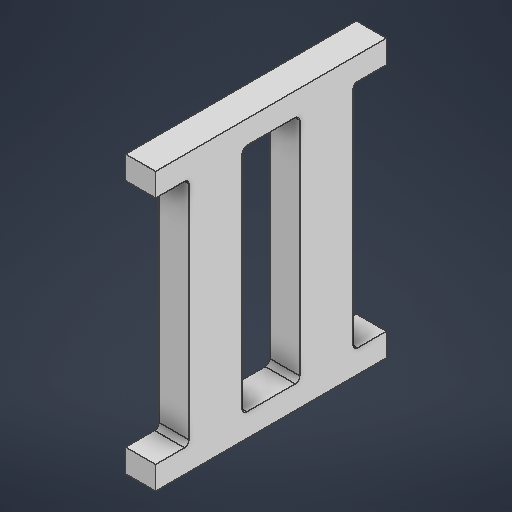
# Autodesk Inventor part: baseCorredera
Saved by Autodesk Inventor 2027.1 (Build 311270010, 270A)
## iProperties
Created: 2026-11-02
Part Number: baseCorredera
Material: Genérico
Document SubType Name: Modeling
Designer: MANGEL
Density: 1 g/cm^3
Appearance: Valor por defecto
Author: MANGEL
Autodesk Inventor part; units mm, degrees
ref_plane "YZ Plane" through (0, 0, 0) normal (1, 0, 0) x (0, 1, 0)
ref_plane "XZ Plane" through (0, 0, 0) normal (0, 1, 0) x (-1, 0, 0)
ref_plane "XY Plane" through (0, 0, 0) normal (0, 0, 1) x (1, 0, 0)
sketch "Boceto2" plane through (0, 0, 0) normal (1, 0, 0) x (0, 1, 0)
  line L0 (-60, 50) -> (60, 50)
  line L1 (60, 50) -> (60, -50)
  line L2 (60, -50) -> (-60, -50)
  line L3 (-60, -50) -> (-60, 50)
  line L4 (-60, 50) -> (60, -50) construction
  line L5 (60, 50) -> (-60, -50) construction
  point P0 (0, 0)
  dimension "d4" = 100
  dimension "d5" = 120
  constraints: 12 end point, 2 midpoint, 2 parallel, 1 horizontal, 1 perpendicular
  measures "d4" distance of L0.end L1.end
  measures "d5" distance of L1.end L2.end
extrude "Extrusión2" add sketch "Boceto2" along normal blind 13
sketch "Boceto3" plane through (13, 0, 0) normal (1, 0, 0) x (0, 0, -1)
  line L0 (-50, 50) -> (-37.5, 50)
  line L1 (-35.5, 48) -> (-35.5, -48)
  line L2 (-37.5, -50) -> (-50, -50)
  line L3 (-50, -50) -> (-50, 50)
  line L4 (-10.5, 50) -> (10.5, 50)
  line L5 (12.5, 48) -> (12.5, -48)
  line L6 (10.5, -50) -> (-10.5, -50)
  line L7 (-12.5, -48) -> (-12.5, 48)
  line L8 (50, 60) -> (-50, 60) construction
  line L9 (0, 60) -> (0, 0) construction
  line L10 (-50, -60) -> (50, -60) construction
  line L11 (50, 50) -> (37.5, 50)
  line L12 (35.5, 48) -> (35.5, -48)
  line L13 (37.5, -50) -> (50, -50)
  line L14 (50, -50) -> (50, 50)
  arc A0 (-35.5, 48) -> (-37.5, 50) centre (-37.5, 48) ccw
  arc A1 (-10.5, 50) -> (-12.5, 48) centre (-10.5, 48) ccw
  arc A2 (12.5, 48) -> (10.5, 50) centre (10.5, 48) ccw
  arc A3 (37.5, 50) -> (35.5, 48) centre (37.5, 48) ccw
  arc A4 (-12.5, -48) -> (-10.5, -50) centre (-10.5, -48) ccw
  arc A5 (10.5, -50) -> (12.5, -48) centre (10.5, -48) ccw
  arc A6 (35.5, -48) -> (37.5, -50) centre (37.5, -48) ccw
  arc A7 (-37.5, -50) -> (-35.5, -48) centre (-37.5, -48) ccw
  line L15 (-50, 60) -> (-50, -60) construction
  point P0 (-35.5, -50)
  point P1 (-35.5, 50)
  point P2 (-12.5, 50)
  point P3 (12.5, -50)
  point P4 (35.5, -50)
  point P5 (35.5, 50)
  dimension "d8" = 10
  dimension "d9" = 10
  dimension "d10" = 23
  dimension "d11" = 71
  dimension "d12" = 23
  dimension "d13" = 2
  constraints: 26 end point, 16 point on circle, 16 tangent, 14 point on line, 8 centre point, 7 equal radius, 4 parallel, 4 symmetric about line, 2 horizontal, 2 perpendicular, 1 collinear, 1 midpoint, 1 vertical
  measures "d8" distance between parallel lines of L8 L0
  measures "d9" distance between parallel lines of L10 L2
  measures "d10" distance between parallel lines of L7 L1
  measures "d11" distance between parallel lines of L12 L1
  measures "d12" distance between parallel lines of L12 L5
  measures "d13" radius of A0
extrude "Extrusión3" cut sketch "Boceto3" against normal blind 13
